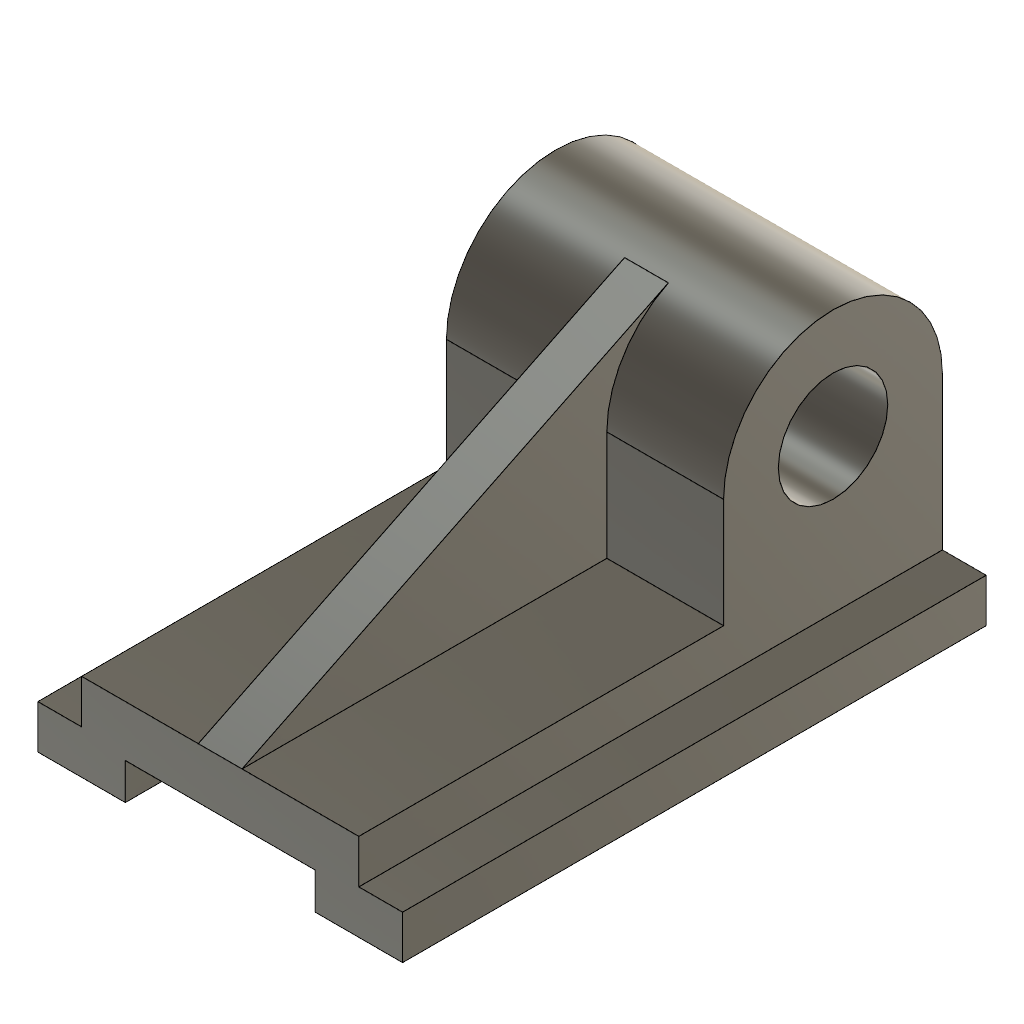
Shape 4 (Autodesk Fusion 360 design; units mm, degrees)
part number: 2026-11-11-08-30-00-408
Autodesk Fusion 360 part; units mm, degrees
sketch "Sketch1" plane through (0, 0, 0) normal (0, 1, 0) x (1, 0, 0)
  line L0 (-50, 6) -> (-50, -6)
  line L1 (50, -6) -> (50, 6)
  line L2 (50, 6) -> (-50, -6) construction
  line L3 (-50, 6) -> (50, -6) construction
  line L4 (26, 6) -> (26, -4)
  line L5 (26, -4) -> (-26, -4)
  line L6 (-26, -4) -> (-26, 6)
  line L7 (-38, -6) -> (-38, -18)
  line L8 (-38, -18) -> (38, -18)
  line L9 (38, -18) -> (38, -6)
  line L10 (-50, -6) -> (-38, -6)
  line L11 (38, -6) -> (50, -6)
  line L12 (50, 6) -> (26, 6)
  line L13 (-26, 6) -> (-50, 6)
  dimension "d1" = 100
  dimension "d2" = 12
  dimension "d3" = 52
  dimension "d4" = 10
  dimension "d5" = 24
  dimension "d6" = 76
  dimension "d7" = 12
  dimension "d8" = 12
  constraint horizontal L12
  constraint perpendicular L0 L13
  constraint parallel L10 L13
  constraint parallel L0 L1
  constraint coincident L2 origin
  constraint coincident L3 origin
  constraint vertical L4
  constraint horizontal L5
  constraint vertical L6
  constraint vertical L7
  constraint horizontal L8
  constraint vertical L9
  constraint collinear L10 L11
  constraint collinear L12 L13
  measures "d1" distance of L0.end L1.start
  measures "d2" distance of L0.start L0.end
  measures "d3" distance of L6.end L4.start
  measures "d4" distance of L6.end L5.end
  measures "d5" distance of L0 L6
  measures "d6" distance of L9.end L7.start
  measures "d7" distance of L9.end L8.end
  measures "d8" distance of L1 L9
extrude "Extrude1" add sketch "Sketch1" along normal blind 160
sketch "Sketch2" plane through (38, 0, 0) normal (1, 0, 0) x (0, 1, 0)
  line L0 (0, 18) -> (0, 6)
  line L1 (0, 6) -> (160, 6)
  line L2 (160, 6) -> (160, 18)
  line L3 (160, 18) -> (0, 18)
  circle A0 centre (130, 48) radius 15
  line L4 (160, 18) -> (160, 48)
  line L5 (130, 82.2338) -> (130, -12.3778) construction
  line L6 (100, 18) -> (100, 48)
  line L7 (92.6617, 48) -> (199.9888, 48) construction
  arc A1 (160, 48) -> (100, 48) centre (130, 48) ccw
  dimension "d11" = 30
  dimension "d12" = 60
  dimension "d13" = 42
  constraint concentric A0 A1
  constraint coincident L2.end L3.start
  constraint parallel L2 L4
  constraint tangent L4 A1
  constraint perpendicular L1 L5
  constraint symmetric L2.end L5 L6.start
  constraint symmetric L4.end L5 L6.end
  constraint tangent L6 A1
  constraint perpendicular L4 L7
  measures "d11" diameter of A0
  measures "d12" diameter of A1
  measures "d13" distance of L1 A0.centre
extrude "Extrude2" add sketch "Sketch2" against normal up to surface (76 mm away) contours L3 L4 L6 A1
sketch "Sketch3" plane through (38, 0, 0) normal (1, 0, 0) x (0, 1, 0)
  circle A0 centre (130, 48) radius 15
  line L0 (0, 18) -> (0, 6)
  line L1 (0, 6) -> (160, 6)
  line L2 (160, 6) -> (160, 48)
  arc A1 (160, 48) -> (100, 48) centre (130, 48) ccw
  line L3 (100, 48) -> (100, 18)
  line L4 (100, 18) -> (0, 18)
  line L5 (0, 18) -> (116.8539, 74.9663)
  constraint coincident L0.start L4.end
  constraint coincident A1 L5.end
  constraint tangent A1 L5
extrude "Extrude3" add sketch "Sketch3" against normal blind 12 from surface at -32 contours A1 L3 L4 L5
equation "d5 = ( ( 100 - 52 ) / 2 ) * 1 mm"
equation "d6 = 32 mm + 32 mm + 12 mm"
